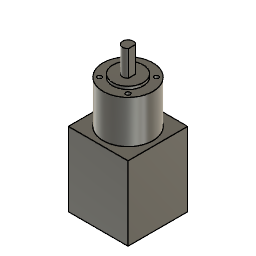
motor_zapfsaeule (Autodesk Fusion 360 design; units mm, degrees)
Autodesk Fusion 360 part; units mm, degrees
sketch "Skizze1" plane through (0, 0, 0) normal (0, 0, 1) x (1, 0, 0)
  line L0 (21, -21) -> (-21, -21)
  line L1 (-21, -21) -> (-21, 21)
  line L2 (-21, 21) -> (21, 21)
  line L3 (21, 21) -> (21, -21)
  line L4 (21, -21) -> (-21, 21) construction
  line L5 (-21, -21) -> (21, 21) construction
  dimension "d1" = 42
  dimension "d2" = 42
  constraint horizontal L0
  constraint perpendicular L0 L1
  constraint parallel L0 L2
  constraint parallel L1 L3
  constraint coincident L4 origin
  constraint coincident L5 origin
  measures "d1" distance of L0.start L2.end
  measures "d2" distance of L1.end L2.end
extrude "Extrusion1" add sketch "Skizze1" along normal blind 52
sketch "Skizze2" plane through (0, 0, 52) normal (0, 0, 1) x (-1, 0, 0)
  line L0 (-21, -21) -> (21, -21)
  line L1 (21, -21) -> (21, 21)
  line L2 (21, 21) -> (-21, 21)
  line L3 (-21, 21) -> (-21, -21)
  circle A0 centre (0, 0) radius 17.5
  dimension "d5" = 35
  constraint coincident A0.centre origin
  measures "d5" diameter of A0
extrude "Extrusion2" add sketch "Skizze2" along normal blind 30 contours A0
sketch "Skizze3" plane through (0, 0, 82) normal (0, 0, 1) x (-1, 0, 0)
  circle A0 centre (0, 0) radius 17.5
  line L0 (-10, 10) -> (10, 10) construction
  line L1 (10, 10) -> (10, -10) construction
  line L2 (10, -10) -> (-10, -10) construction
  line L3 (-10, -10) -> (-10, 10) construction
  line L4 (-10, 10) -> (10, -10) construction
  line L5 (10, 10) -> (-10, -10) construction
  circle A1 centre (10, -10) radius 1.5
  circle A2 centre (-10, -10) radius 1.5
  circle A3 centre (-10, 10) radius 1.5
  circle A4 centre (10, 10) radius 1.5
  dimension "d8" = 20
  dimension "d9" = 20
  dimension "d10" = 3
  dimension "d11" = 3
  dimension "d12" = 3
  dimension "d13" = 3
  constraint horizontal L0
  constraint perpendicular L0 L1
  constraint parallel L0 L2
  constraint parallel L1 L3
  constraint coincident L4 A0.centre
  constraint coincident L5 A0.centre
  constraint coincident A0.centre origin
  constraint coincident L1.end L2.start
  constraint coincident L2.end L3.start
  constraint coincident L0.start L3.end
  constraint coincident L0.end L1.start
  measures "d8" distance of L0.end L1.end
  measures "d9" distance of L1.end L2.end
  measures "d10" diameter of A1
  measures "d11" diameter of A2
  measures "d12" diameter of A3
  measures "d13" diameter of A4
extrude "Extrusion3" cut sketch "Skizze3" against normal blind 5 contours A1 | A2 | A3 | A4
sketch "Skizze4" plane through (0, 0, 82) normal (0, 0, 1) x (-1, 0, 0)
  circle A0 centre (-10, -10) radius 1.5
  circle A1 centre (-10, 10) radius 1.5
  circle A2 centre (10, -10) radius 1.5
  circle A3 centre (10, 10) radius 1.5
  circle A4 centre (0, 0) radius 17.5
  circle A5 centre (0, 0) radius 10.75
  dimension "d16" = 21.5
  constraint concentric A4 A5
  measures "d16" diameter of A5
extrude "Extrusion4" add sketch "Skizze4" along normal blind 2 contours A5
sketch "Skizze5" plane through (0, 0, 84) normal (0, 0, 1) x (-1, 0, 0)
  circle A0 centre (0, 0) radius 10.75
  circle A1 centre (0, 0) radius 3.85
  line L0 (-2.8395, -2.6) -> (-2.8395, 2.6)
  dimension "d19" = 7.7
  dimension "d20" = 5.2
  constraint concentric A0 A1
  constraint coincident A1 L0.start
  constraint coincident A1 L0.end
  constraint vertical L0
  measures "d19" diameter of A1
  measures "d20" distance of L0.start L0.end
extrude "Extrusion5" add sketch "Skizze5" along normal blind 18 contours A1 L0 picked at (-0.908, 1.3011)
